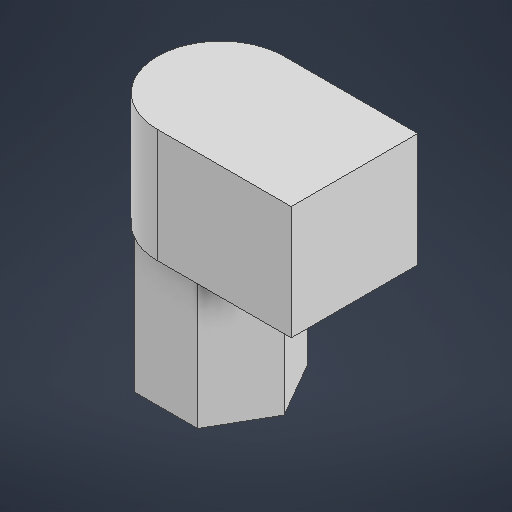
# Autodesk Inventor part: Connector
Saved by Autodesk Inventor 2027.1 (Build 311270010, 270A)
## iProperties
Created: 2026-10-21
Part Number: Connector
Material: Generic
Document SubType Name: Modeling
Designer: MSIPC
Density: 1 g/cm^3
Appearance: Default
Author: MSIPC
Autodesk Inventor part; units mm, degrees
ref_plane "YZ Plane" through (0, 0, 0) normal (1, 0, 0) x (0, 1, 0)
ref_plane "XZ Plane" through (0, 0, 0) normal (0, 1, 0) x (-1, 0, 0)
ref_plane "XY Plane" through (0, 0, 0) normal (0, 0, 1) x (1, 0, 0)
sketch "Sketch1" plane through (0, 0, 0) normal (0, 1, 0) x (-1, 0, 0)
  line L0 (3.5796, 0) -> (1.7898, -3.1)
  line L1 (1.7898, -3.1) -> (-1.7898, -3.1)
  line L2 (-1.7898, -3.1) -> (-3.5796, 0)
  line L3 (-3.5796, 0) -> (-1.7898, 3.1)
  line L4 (-1.7898, 3.1) -> (1.7898, 3.1)
  line L5 (1.7898, 3.1) -> (3.5796, 0)
  line L6 (4.7343, 0) -> (2.3671, -4.1)
  line L7 (2.3671, -4.1) -> (-2.3671, -4.1)
  line L8 (-2.3671, -4.1) -> (-4.7343, 0)
  line L9 (-4.7343, 0) -> (-2.3671, 4.1)
  line L10 (-2.3671, 4.1) -> (2.3671, 4.1)
  line L11 (2.3671, 4.1) -> (4.7343, 0)
  line L12 (4.7343, 0) -> (2.3671, -4.1)
  line L13 (2.3671, -4.1) -> (-2.3671, -4.1)
  line L14 (-2.3671, -4.1) -> (-4.7343, 0)
  line L15 (-4.7343, 0) -> (-2.3671, 4.1)
  line L16 (-2.3671, 4.1) -> (2.3671, 4.1)
  line L17 (2.3671, 4.1) -> (4.7343, 0)
  point P0 (0, 0)
  point P1 (0, 0)
  point P2 (0, 0)
  dimension "d10" = 6.2
  dimension "d11" = 1
  constraints: 36 end point, 2 coincident, 31 other
  measures "d10" distance between parallel lines of L0 L3
  measures "d11" distance between parallel lines of L5 L11
extrude "Extrusion1" add sketch "Sketch1" along normal blind 10
sketch "Sketch5" plane through (0, 10, 0) normal (0, 1, 0) x (1, 0, 0)
  line L0 (-4.7343, 0) -> (-2.3671, -4.1) projected
  circle A0 centre (0, 0) radius 4.7343
  line L1 (0, -4.7343) -> (0, 4.7343)
  line L2 (0, 4.7343) -> (10, 4.7343)
  line L3 (10, 4.7343) -> (10, -4.7343)
  line L4 (10, -4.7343) -> (0, -4.7343)
  dimension "d12" = 10
  constraints: 8 end point, 3 point on circle, 2 parallel, 1 centre point, 1 coincident, 1 perpendicular, 1 vertical
  measures "d12" distance of L1.end L2.end
extrude "Extrusion4" add sketch "Sketch5" along normal blind 8.5
body "Solid1"
